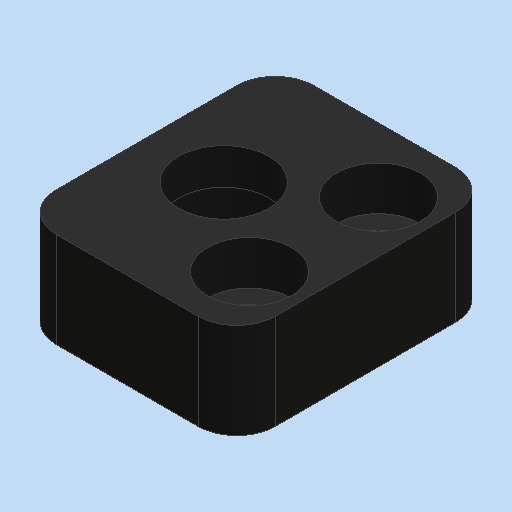
# Autodesk Inventor part: MN0555AN105_G01_102
Saved by Autodesk Inventor 2023.3 (Build 273359000, 359)
## iProperties
Part Number: MN0555AN105_G01_102
Material: Kst - TECAFORM AH ELS schwarz
Description: =<RBPARTNOTITLE2>
Document SubType Name: Modeling
Designer: ric7an
Mass: 2.56842 g
Surface Area: 14.6225 cm^2
Volume: 1.82157 cm^3
Density: 1.41 g/cm^3
Appearance: schwarz AnP
RBDOCUMENTTYPE: DRF
RBDOCUMENTVERSION: 00
RBDRAWINGMAINSCALE: 1:1
RBDRAWINGMISSINGSPEC: --
RBDRAWINGVOLUME: --
RBGBEDGESIN1: +0,5
RBGBEDGESIN2: +0,2
RBGBEDGESOUT1: -0,3
RBGBEDGESOUT2: -0,1
RBMATERIAL: =<Material>
RBMATMEETS: --
RBMATNO: =<Part Number>
RBPARTMADEOF: 7,4 x 20 x 17 (FM)
RBPARTNO: SIEHE MNR
RBPARTNOTITLE1: manufactured part
RBPARTNOTITLE2: Anfertigungsteil
RBPARTSAFETYINDICATOR: --
RBSURFACE: --
RBSURFACE2: --
RBZEDGESNORM: ISO13715:2002-06
RBZGENDIMCLASS: m
RBZGENDIMNORM: ISO 2768-1:1989-11
RBZGENGEOCLASS: H
RBZGENGEONORM: ISO 2768-2:1989-11
RBZSURFACENORM: ISO13D2:2002-02
RBZTOLERANCENORM: ISO 14405-1:2010-12
AnP_Material: =<Material>
AnP_TemplVers: 20190222
AnP_Kategorie: 1
MaxAbmaße: 7,4 x 20 x 17 (FM)
Author: ric7an
Keywords: =<RBPARTMADEOF>
Comments: =<RBSURFACE2>
Revision Number: 01
Autodesk Inventor part; units mm, degrees
ref_plane "YZ Plane" through (0, 0, 0) normal (1, 0, 0) x (0, 1, 0)
ref_plane "XZ Plane" through (0, 0, 0) normal (0, 1, 0) x (-1, 0, 0)
ref_plane "XY Plane" through (0, 0, 0) normal (0, 0, 1) x (1, 0, 0)
sketch "Skizze1" plane through (0, 0, 0) normal (0, 0, 1) x (1, 0, 0)
  line L0 (-8.5, 10) -> (8.5, 10)
  line L1 (8.5, 10) -> (8.5, -10)
  line L2 (8.5, -10) -> (-8.5, -10)
  line L3 (-8.5, -10) -> (-8.5, 10)
  line L4 (0, 14) -> (0, -14) projected
  line L5 (-11.9, 0) -> (11.9, 0) projected
  point P0 (0, 0)
  dimension "d0" = 20
  dimension "d1" = 17
  constraints: 8 end point, 2 parallel, 1 horizontal, 1 perpendicular, 2 other
  measures "d0" distance of L0.end L1.end
  measures "d1" distance of L0.start L0.end
extrude "Extrusion1" add sketch "Skizze1" along normal blind 7.4
sketch "Skizze2" plane through (0, 0, 7.4) normal (0, 0, 1) x (1, 0, 0)
  line L0 (-11.9, 0) -> (11.9, 0) projected
  line L1 (0, 14) -> (0, -14) projected
  point P0 (-2.5, 0)
  dimension "d39" = 2.5
  constraints: 1 point on line
  measures "d39" distance from line of L1 point (-2.5, 0)
hole "Bohrung1" at (-2.5, 0, 7.4) direction (0, 0, -1) diameter 7 end through all
sketch "Skizze3" plane through (0, 0, 7.4) normal (0, 0, 1) x (1, 0, 0)
  line L0 (0, 14) -> (0, -14) projected
  line L1 (-11.9, 0) -> (11.9, 0) projected
  point P0 (0, 0)
  point P1 (4.5, -5)
  point P2 (4.5, 5)
  dimension "d38" = 10
  dimension "d40" = 4.5
  constraints: 1 symmetric about line, 1 vertical alignment
  measures "d38" distance of point (4.5, -5) point (4.5, 5)
  measures "d40" distance from line of point (4.5, -5) L0
hole "Bohrung2" at (4.5, -5, 7.4) at (4.5, 5, 7.4) direction (0, 0, -1) diameter 3.4 end through all counterbore diameter 6.5 counterbore depth 3.4 clearance for "Inbusschraube ISO 4762  versenkt" size "M3" standard "ISO"
fillet "Rundung1" radius 3 4 edges at (-8.5, 10, 3.7) (8.5, 10, 3.7) (8.5, -10, 3.7) (-8.5, -10, 3.7)
hole "Bohrung4" at (-2.5, 0, 0) direction (0, 0, 1) diameter 8 depth 4.6
